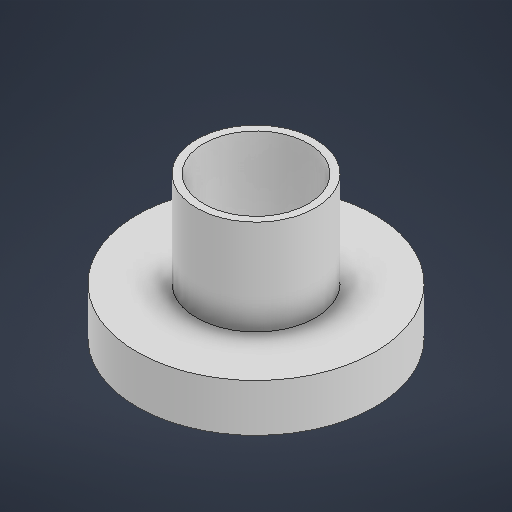
# Autodesk Inventor part: adaptateur_axe_roulements
Saved by Autodesk Inventor 2026 (Build 300175000, 175)
## iProperties
Created: 2025-05-14
Part Number: adaptateur_axe_roulements
Material: Générique
Document SubType Name: Modeling
Designer: Diogo
Density: 1 g/cm^3
Appearance: Par défaut
Author: Diogo
Autodesk Inventor part; units mm, degrees
ref_plane "YZ Plane" through (0, 0, 0) normal (1, 0, 0) x (0, 1, 0)
ref_plane "XZ Plane" through (0, 0, 0) normal (0, 1, 0) x (-1, 0, 0)
ref_plane "XY Plane" through (0, 0, 0) normal (0, 0, 1) x (1, 0, 0)
sketch "Esquisse3" plane through (0, 0, 0) normal (0, 0, 1) x (1, 0, 0)
  line L0 (2.2, 0) -> (2.2, 6)
  line L1 (2.2, 6) -> (2.5, 6)
  line L2 (2.5, 6) -> (2.5, 2)
  line L3 (2.5, 2) -> (5, 2)
  line L4 (5, 2) -> (5, 0)
  line L5 (5, 0) -> (2.2, 0)
  line L6 (0, -1.2) -> (0, 7.2) projected
  point P0 (0, 0)
  dimension "d9" = 6
  dimension "d10" = 0.3
  dimension "d11" = 4
  dimension "d12" = 5
  dimension "d13" = 2.2
  constraints: 12 end point, 5 perpendicular, 1 vertical
  measures "d9" distance of L0.start L0.end
  measures "d10" distance of L0.end L1.end
  measures "d11" distance of L1.end L2.end
  measures "d12" distance from line of point (0, 0) L4
  measures "d13" distance from line of point (0, 0) L0
revolve "Révolution1" add sketch "Esquisse3" angle 360 about axis through (0, -10, 0) along (0, 1, 0)
